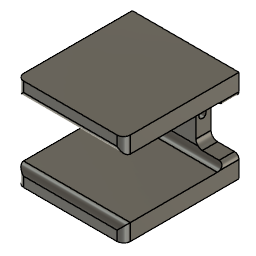
Amazing Wheel Assembly (Autodesk Fusion 360 archive; units mm, degrees)
design "Bracket For Yellow Motors"
Autodesk Fusion 360 part; units mm, degrees
sketch "Sketch1" plane through (0, 0, 0) normal (0, 0, 1) x (1, 0, 0)
  line L0 (0, 0) -> (41.148, 0)
  line L1 (41.148, 0) -> (41.148, 44.45)
  line L2 (41.148, 44.45) -> (0, 44.45)
  line L3 (0, 44.45) -> (0, 0)
  dimension "d1" = 41.148
  dimension "d2" = 44.45
  constraint horizontal L0
  constraint vertical L1
  constraint horizontal L2
  constraint vertical L3
  constraint coincident L0.start L3.end
  measures "d1" distance of L0.start L0.end
  measures "d2" distance of L0.start L2.end
extrude "Extrude1" add sketch "Sketch1" along normal blind 6.35
sketch "Sketch2" plane through (0, 0, 6.35) normal (0, 0, 1) x (-1, 0, 0)
  line L0 (0, -44.45) -> (0, 0)
  line L1 (0, 0) -> (-41.148, 0)
  line L2 (-41.148, 0) -> (-41.148, -44.45)
  line L3 (-41.148, -44.45) -> (0, -44.45)
  line L4 (0, 0) -> (0, -38.608) construction
  line L5 (0, -38.608) -> (-41.148, -38.608)
  line L6 (-41.148, -38.608) -> (-41.148, -44.45)
  line L7 (-41.148, -44.45) -> (0, -44.45)
  line L8 (0, -44.45) -> (0, -38.608)
  dimension "d5" = 38.608
  constraint coincident L0.end L1.start
  constraint perpendicular L1 L4
  constraint horizontal L5
  constraint vertical L6
  constraint horizontal L7
  constraint vertical L8
  constraint coincident L2.end L3.start
  measures "d5" distance of L0.end L4.end
extrude "Extrude2" add sketch "Sketch2" along normal blind 22.86 contours L0 L2 L3 L5 L6 L7 L8
sketch "Sketch3" plane through (0, 0, 29.21) normal (0, 0, 1) x (-1, 0, 0)
  line L0 (0, -44.45) -> (0, -38.608)
  line L1 (0, -38.608) -> (-41.148, -38.608)
  line L2 (-41.148, -38.608) -> (-41.148, -44.45)
  line L3 (-41.148, -44.45) -> (0, -44.45)
  line L4 (-41.148, -44.45) -> (0, -44.45)
  line L5 (0, -44.45) -> (0, 0)
  line L6 (0, 0) -> (-41.148, 0)
  line L7 (-41.148, 0) -> (-41.148, -44.45)
  constraint horizontal L4
  constraint vertical L5
  constraint horizontal L6
  constraint vertical L7
  constraint coincident L5.end L6.start
  constraint coincident L2.end L3.start
extrude "Extrude3" add sketch "Sketch3" along normal blind 6.35
sketch "Sketch4" plane through (0, 44.45, 0) normal (0, 1, 0) x (-1, 0, 0)
  line L0 (-41.148, 0) -> (0, 0)
  line L1 (0, 0) -> (0, 35.56)
  line L2 (0, 35.56) -> (-41.148, 35.56)
  line L3 (-41.148, 35.56) -> (-41.148, 0)
  line L4 (-41.148, 17.78) -> (-33.528, 17.78) construction
  line L5 (-33.528, 17.78) -> (-30.353, 17.78) construction
  line L6 (-30.353, 8.255) -> (-41.148, 8.255)
  line L7 (-41.148, 8.255) -> (-41.148, 27.305)
  line L8 (-41.148, 27.305) -> (-30.353, 27.305)
  line L9 (-30.353, 27.305) -> (-30.353, 8.255)
  line L10 (-20.574, 35.56) -> (-20.574, 0) construction
  line L11 (-10.795, 27.305) -> (-10.795, 8.255)
  line L12 (0, 27.305) -> (-10.795, 27.305)
  line L13 (0, 8.255) -> (0, 27.305)
  line L14 (-10.795, 8.255) -> (0, 8.255)
  dimension "d10" = 7.62
  dimension "d11" = 3.175
  dimension "d13" = 19.05
  constraint midpoint L3 L4.start
  constraint perpendicular L3 L4
  constraint horizontal L5
  constraint horizontal L6
  constraint vertical L7
  constraint horizontal L8
  constraint vertical L9
  constraint midpoint L5.end L9
  constraint midpoint L2 L10.start
  constraint midpoint L0 L10.end
  constraint symmetric L6.start L10 L11.end
  constraint symmetric L6.end L10 L13.start
  constraint symmetric L7.end L10 L12.start
  constraint symmetric L8.end L10 L11.start
  measures "d10" distance of L4.start L4.end
  measures "d11" distance of L4.end L5.end
  measures "d13" distance of L6.start L8.end
extrude "Extrude4" cut sketch "Sketch4" against normal up to surface (5.842 mm away) contours L3 L6 L7 L8 L9 | L1 L11 L12 L13 L14
fillet "Fillet2" radius 2.54 6 edges at (20.574, 0, 29.21) (41.148, 0, 32.385) (0, 0, 32.385) (20.574, 0, 6.35) (41.148, 0, 3.175) (0, 0, 3.175)
fillet "Fillet4" radius 2.54 4 edges at (30.353, 41.529, 8.255) (10.795, 41.529, 8.255) (10.795, 41.529, 27.305) (30.353, 41.529, 27.305)
fillet "Fillet4" radius 2.54 2 edges at (20.574, 38.608, 6.35) (20.574, 38.608, 29.21)
fillet "Fillet5" radius 1.778 4 edges at (41.148, 41.4887, 8.255) (41.148, 41.4887, 27.305) (0, 41.4887, 8.255) (0, 41.4887, 27.305)
sketch "Sketch5" plane through (30.353, 0, 0) normal (1, 0, 0) x (0, 1, 0)
  line L0 (44.45, 24.765) -> (38.608, 24.765)
  line L1 (38.608, 24.765) -> (38.608, 10.795)
  line L2 (38.608, 10.795) -> (44.45, 10.795)
  line L3 (44.45, 10.795) -> (44.45, 24.765)
  line L4 (38.608, 17.78) -> (44.45, 17.78) construction
  circle A0 centre (41.151, 17.78) radius 1.4
  line L5 (38.608, 17.78) -> (39.751, 17.78) construction
  dimension "d28" = 2.8
  dimension "d29" = 1.143
  constraint midpoint L1 L4.start
  constraint midpoint L3 L4.end
  constraint coincident L4 A0.centre
  constraint coincident A0 L5.end
  constraint coincident L4 L5.end
  measures "d28" diameter of A0
  measures "d29" distance of L4.start L5.end
extrude "Extrude5" cut sketch "Sketch5" against normal up to surface (19.558 mm away) contours A0

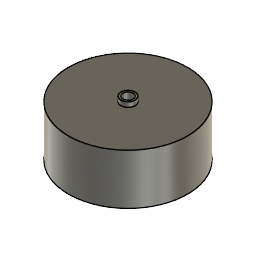
design "Yellow Motor Wheel"
Autodesk Fusion 360 part; units mm, degrees
sketch "Sketch4" plane through (0, 0, 0) normal (0, 0, 1) x (1, 0, 0)
  circle A0 centre (0, 0) radius 31.75
  dimension "d14" = 63.5
  constraint coincident A0.centre origin
  measures "d14" diameter of A0
extrude "Extrude4" add sketch "Sketch4" along normal blind 26.924
sketch "Sketch5" plane through (0, 0, 26.924) normal (0, 0, 1) x (-1, 0, 0)
  circle A0 centre (0, 0) radius 31.75
  circle A1 centre (0, 0) radius 2.7
  circle A2 centre (0, 0) radius 3.81
  dimension "d17" = 5.4
  dimension "d18" = 7.62
  constraint concentric A0 A1
  constraint concentric A1 A2
  measures "d17" diameter of A1
  measures "d18" diameter of A2
extrude "Extrude5" add sketch "Sketch5" along normal blind 2.54 contours A2
extrude "Extrude6" cut 1 faces at (-0.0791, 0.5246, 26.924) along direction (0, 0, -1) blind 5.36
equation "d21 = -0.0079 m + 0.1 in"
